DeskOrganizer (Autodesk Fusion 360 design; units mm, degrees)
Autodesk Fusion 360 part; units mm, degrees
sketch "Sketch1" plane through (0, 0, 0) normal (0, 1, 0) x (1, 0, 0)
  circle A0 centre (0, 0) radius 42
  circle A1 centre (0, 0) radius 40
  line L0 (0, 0) -> (25.482, -25.482)
  line L1 (0, 0) -> (36.037, 0) construction
  circle A2 centre (25.482, -25.482) radius 32
  circle A3 centre (25.482, -25.482) radius 30
  line L2 (0, 0) -> (-15, -52.5)
  circle A4 centre (-15, -52.5) radius 20
  circle A5 centre (-15, -52.5) radius 22
  line L3 (-40.3979, 11.4894) -> (0, 0)
  line L4 (25.482, -25.482) -> (44.1863, -51.4464)
  arc A6 (-40.3979, 11.4894) -> (44.1863, -51.4464) centre (-8.9995, -34.6193) ccw
  arc A7 (-40.3979, 11.4894) -> (-40.8991, 9.5533) centre (0, 0) ccw
  arc A8 (42.5278, -52.5641) -> (44.1863, -51.4464) centre (25.482, -25.482) ccw
  line L5 (-37.2559, -82.7177) -> (-36.4905, -80.8699)
  line L6 (-37.2559, -82.7177) -> (-35.2559, -82.7177) construction
  arc A9 (-40.8991, 9.5533) -> (42.5278, -52.5641) centre (-8.6322, -34.1926) ccw
  dimension "d1" = 84
  dimension "d2" = 80
  dimension "d3" = 45
  dimension "d4" = 64
  dimension "d5" = 60
  dimension "d6" = 40
  dimension "d7" = 44
  dimension "d8" = 2
  dimension "d9" = 2
  dimension "d10" = 2
  dimension "d11" = 67.5
  constraint coincident A0.centre A1.centre
  constraint horizontal L1
  constraint coincident L0.end A2.centre
  constraint concentric A2 A3
  constraint coincident L2.end A4.centre
  constraint concentric A4 A5
  constraint coincident A0 L3.start
  constraint coincident A2 L4.end
  constraint coincident A0 A7.end
  constraint coincident A2 A8.start
  constraint horizontal L6
  constraint coincident A6 L5.start
  constraint coincident L5.end A9
  measures "d1" diameter of A0
  measures "d2" diameter of A1
  measures "d3" angle of L0 L1
  measures "d4" diameter of A2
  measures "d5" diameter of A3
  measures "d6" diameter of A4
  measures "d7" diameter of A5
  measures "d8" distance of L3.start A7.end
  measures "d9" distance of L4.end A8.start
  measures "d10" distance of L5.start L5.end
  measures "d11" angle of L5 L6
extrude "Extrude1" add sketch "Sketch1" along normal blind 2 makes body 1
extrude "Extrude2" add sketch "Sketch1" along normal blind 82 contours A0 A1 A2 L3 bodies 1
extrude "Extrude3" add sketch "Sketch1" along normal blind 5 contours A0 A6 A7 L5 A9 | A2 A6 A8 L5 A9 bodies 1
extrude "Extrude4" add sketch "Sketch1" along normal blind 62 contours A0 A2 A3 L4 bodies 1
extrude "Extrude5" add sketch "Sketch1" along normal blind 72 contours A0 A1 A2 A3 | A1 L0 A2 A3 | L0 A2 A3 L2 A5 | A2 A3 A4 A5 | A2 A3 A4 A5 | A0 A1 A2 A3 | A0 A2 A3 A4 | A1 A2 A3 A4 bodies 1
extrude "Extrude6" add sketch "Sketch1" along normal blind 72 contours A0 A1 A2 A3 | A0 A1 A3 L4 | A0 A1 A5 L4 | A0 A1 A2 A3 | A0 A1 A4 A5 | A0 A1 A3 A4 picked at (2.5785, -41.2329) bodies 1
extrude "Extrude7" cut sketch "Sketch1" along normal blind 72 contours A2 A3 A4 A5 | A0 A2 A3 A4 picked at (5.3944, -49.1924) bodies 1
extrude "Extrude8" add sketch "Sketch1" along normal blind 2 contours A2 A3 A4 A5 | A0 A2 A3 A4 picked at (5.3944, -49.1924) bodies 1
extrude "Extrude9" add sketch "Sketch1" along normal blind 82 contours A0 A1 A5 L3 A7 | A0 A1 A4 A5 | A0 A1 L2 A4 | A0 A1 A2 L2 | A0 A1 A2 A3 picked at (-23.9727, -33.6469) picked at (-1.2985, -41.3093) bodies 1
extrude "Extrude10" add sketch "Sketch1" along normal blind 40 contours A0 A2 A4 A5 bodies 1
extrude "Extrude11" add sketch "Sketch1" along normal blind 62 contours A2 A3 A5 L4 A8 | A2 A3 A4 A5 | A0 A2 A3 A4 picked at (5.3944, -49.1924) bodies 1
extrude "Extrude12" add sketch "Sketch1" along normal blind 50 contours A1 L0 A3 L4 | A1 L0 A3 A5 L4 | A1 A3 A4 A5 | A1 A3 A4 bodies 1
extrude "Extrude13" add 1 faces at (7.4683, 72, 39.8936) along direction (0, 1, 0) blind 10 on bodies 1 bodies 1
fillet "Fillet1" radius 14.5 1 faces at (20.2287, 50, 20.2287) on bodies 1
extrude "Extrude14" cut 1 faces at (40.0862, 82, -6.3922) along direction (0, -1, 0) blind 6 on bodies 1 bodies 1
extrude "Extrude15" add sketch "Sketch1" along normal blind 10 separate body makes body 2
ref_plane "WorkPlane1" through (-32.1739, 5.0787, -26.9971) normal (-0.766044, 0, -0.642788) x (0.642788, 0, -0.766044)
sketch "Sketch2" plane through (-32.1739, 5.0787, -26.9971) normal (-0.766044, 0, -0.642788) x (0.642788, 0, -0.766044)
  line L0 (42, 5) -> (-88, 5)
  line L1 (-88, 5) -> (-88, -5)
  line L2 (-88, -5) -> (42, -5)
  line L3 (42, -5) -> (42, 5)
  line L4 (42, -5) -> (-88, 5)
  line L5 (-88, -5) -> (-89, -5)
  line L6 (-89, -5) -> (-89, 5)
  line L7 (-89, 5) -> (-88, 5)
  line L8 (-88, 5) -> (-88, -5)
  dimension "d46" = 10
  dimension "d47" = 130
  dimension "d48" = 1
  dimension "d49" = 10
  constraint horizontal L0
  constraint vertical L1
  constraint horizontal L2
  constraint vertical L3
  constraint horizontal L5
  constraint vertical L6
  constraint horizontal L7
  constraint vertical L8
  measures "d46" distance of L0.end L1.end
  measures "d47" distance of L1.end L2.end
  measures "d48" distance of L1.end L5.end
  measures "d49" distance of L1.end L0.end
extrude "Extrude17" cut sketch "Sketch2" against normal blind 191 contours L1 L2 L4 L8 | L1 L5 L6 L7 L8 bodies 2
extrude "Extrude16" cut sketch "Sketch2" against normal blind 175 contours L1 L2 L4 L8 bodies 2
fillet "Fillet2" radius 12 1 edges at (-41.0957, 2, 77.7928) on bodies 1
extrude "Extrude18" add sketch "Sketch1" along normal blind 76 contours A2 L2 bodies 1 2
fillet "Fillet6" radius 347.5 1 edges at (41.9546, 31, -1.9525) on bodies 1
fillet "Fillet4" radius 230.5 1 edges at (-40.3979, 2.7637, -11.4894) on bodies 1
fillet "Fillet5" radius 248 1 edges at (44.1863, 3.0006, 51.4464) on bodies 1
fillet "Fillet7" radius 1 10 edges at (42.0753, 62, 52.8437) (44.8987, 62, -4.7584) (46.6952, 62, 46.6952) (-39.1577, 76, -15.1878) (28.2843, 76, 28.2843) (4.2688, 76, 4.2688) (2.8546, 76, 2.8546) (-28.2843, 76, -28.2843) (-25.7769, 40, 71.6796) (-24.4407, 40, 70.1316) on bodies 1
sketch "Sketch3" plane through (0, 62, 0) normal (0, 1, 0) x (-1, 0, 0)
  arc A0 (-51.9176, 9.2906) -> (-41.9932, -0.755) centre (-25.482, 25.482) ccw
  arc A1 (-40.6647, -10.5063) -> (-51.9176, 9.2906) centre (-349.1046, -172.7317) ccw
  arc A2 (-41.9932, -0.755) -> (-40.6647, -10.5063) centre (0, 0) ccw
  line L0 (-41.9932, -0.755) -> (-42.3533, -0.9291)
  line L1 (-41.9616, -1.7952) -> (-42.3616, -1.7952)
  line L2 (-41.7201, -4.8406) -> (-42.1201, -4.8406)
  line L3 (-46.1294, -2.4722) -> (-44.8923, -1.8169)
  line L4 (-45.5784, 1.8783) -> (-45.8539, 1.5883)
  arc A3 (-51.6326, 8.8245) -> (-42.3533, -0.9291) centre (-29.6065, 20.4886) ccw
  arc A4 (-40.6647, -10.5063) -> (-51.6326, 8.8245) centre (-132.2279, -49.6805) ccw
  arc A5 (-42.3533, -0.9291) -> (-40.6647, -10.5063) centre (-16.8617, -1.3719) ccw
  dimension "d78" = 0.4
  dimension "d79" = 0.4
  dimension "d80" = 0.4
  dimension "d81" = 1.4
  dimension "d82" = 0.4
  constraint coincident A0.end A2.start
  constraint coincident A2 L1.start
  constraint horizontal L1
  constraint coincident A2 L2.start
  constraint horizontal L2
  constraint coincident A0 L4.start
  constraint coincident L4.end A3
  constraint coincident A1 A3.start
  constraint coincident L3.end A4
  constraint coincident A1.start A2.end
  constraint coincident L2.end A5
  measures "d78" distance of A0.end L0.end
  measures "d79" distance of L1.start L1.end
  measures "d80" distance of L2.start L2.end
  measures "d81" distance of L3.start L3.end
  measures "d82" distance of L4.start L4.end
extrude "Extrude19" cut sketch "Sketch3" against normal blind 20 contours A3 A4 A5 bodies 1
extrude "Extrude20" cut sketch "Sketch1" along normal blind 45 contours A1 L0 A3 L4 | A1 L0 A3 A5 L4 | A1 A3 A4 A5 | A1 A3 A4 bodies 1
sketch "Sketch4" plane through (0, 45, 0) normal (0, -1, 0) x (1, 0, 0)
  arc A0 (39.9925, -0.7753) -> (-0.7753, 39.9925) centre (0, 0) ccw
  arc A1 (-0.7753, 39.9925) -> (39.9925, -0.7753) centre (25.482, 25.482) ccw
  circle A2 centre (4.5, 28) radius 1
  circle A3 centre (10, 22) radius 1
  circle A4 centre (16, 16) radius 1
  circle A5 centre (21.5, 11) radius 1
  circle A6 centre (27, 7) radius 1
  circle A7 centre (32.5, 3) radius 1
  circle A8 centre (36.5, 1) radius 1
  circle A9 centre (7.5, 5) radius 1
  circle A10 centre (13.5, 11) radius 1
  circle A11 centre (20, 21.5) radius 1
  circle A12 centre (23, 26.5) radius 1
  circle A13 centre (0.5, 34) radius 1
  dimension "d64" = 2
  dimension "d65" = 2
  dimension "d66" = 2
  dimension "d67" = 2
  dimension "d68" = 2
  dimension "d69" = 2
  dimension "d70" = 2
  dimension "d71" = 2
  dimension "d72" = 2
  dimension "d73" = 2
  dimension "d74" = 2
  dimension "d75" = 2
  measures "d64" diameter of A2
  measures "d65" diameter of A3
  measures "d66" diameter of A4
  measures "d67" diameter of A5
  measures "d68" diameter of A6
  measures "d69" diameter of A7
  measures "d70" diameter of A8
  measures "d71" diameter of A9
  measures "d72" diameter of A10
  measures "d73" diameter of A11
  measures "d74" diameter of A12
  measures "d75" diameter of A13
extrude "Extrude21" add sketch "Sketch4" along normal blind 45 contours A2 | A3 | A4 | A5 | A6 | A7 | A8 | A9 | A10 | A11 | A12 | A13 bodies 1
fillet "Fillet8" radius 0.2 2 edges at (40.6647, 52, -10.5063) (48.4674, 52, 4.1955) on bodies 1
named bodies: "Desk Organizer"
